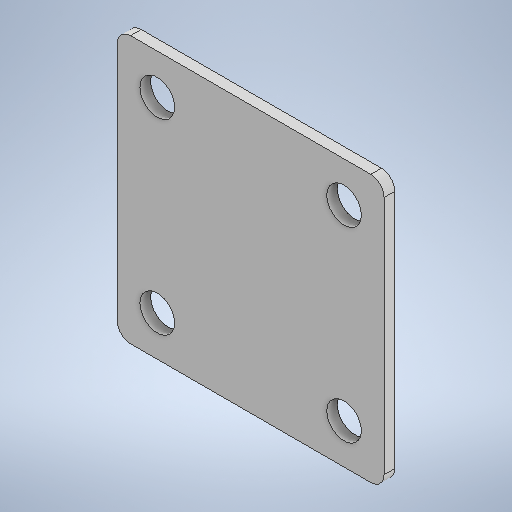
# Autodesk Inventor part: GBK-RK-0832 ring plate
Saved by Autodesk Inventor 2026 (Build 300175000, 175)
## iProperties
Created: 2024-05-23
Part Number: GBK-RK-0832 ring plate
Material: Generic
Document SubType Name: Sheet Metal
Designer: user
Mass: 0.559799 g
Surface Area: 23.3947 cm^2
Volume: 0.559799 cm^3
Density: 1 g/cm^3
Flat Pattern Width: 10 cm
Flat Pattern Length: 10 cm
Flat Pattern Area: 100 cm^2
Sheet Metal Rule: По умолчанию_мм
Sheet Metal Width: 100,000 мм
Sheet Metal Length: 100,000 мм
Sheet Metal Area: 10000,000 мм^2
Appearance: По умолчанию
Author: admin
Autodesk Inventor part; units mm, degrees
ref_plane "YZ Plane" through (0, 0, 0) normal (1, 0, 0) x (0, 1, 0)
ref_plane "XZ Plane" through (0, 0, 0) normal (0, 1, 0) x (-1, 0, 0)
ref_plane "XY Plane" through (0, 0, 0) normal (0, 0, 1) x (1, 0, 0)
sketch "Sketch1" plane through (0, 0, 0) normal (0, 0, 1) x (1, 0, 0)
  line L0 (-45, 50) -> (45, 50)
  line L1 (50, 45) -> (50, -45)
  line L2 (45, -50) -> (-45, -50)
  line L3 (-50, -45) -> (-50, 45)
  line L4 (-50, 50) -> (50, -50) construction
  line L5 (50, 50) -> (-50, -50) construction
  line L6 (0, 50) -> (0, -50) construction
  circle A0 centre (-35, -35) radius 6.5
  circle A1 centre (-35, 35) radius 6.5
  circle A2 centre (35, -35) radius 6.5
  circle A3 centre (35, 35) radius 6.5
  line L7 (35, 35) -> (-35, 35) construction
  line L8 (-35, 35) -> (-35, -35) construction
  line L9 (-35, -35) -> (35, -35) construction
  line L10 (35, -35) -> (35, 35) construction
  line L11 (35, 35) -> (-35, -35) construction
  line L12 (-35, 35) -> (35, -35) construction
  arc A4 (-45, 50) -> (-50, 45) centre (-45, 45) ccw
  arc A5 (50, 45) -> (45, 50) centre (45, 45) ccw
  arc A6 (45, -50) -> (50, -45) centre (45, -45) ccw
  arc A7 (-50, -45) -> (-45, -50) centre (-45, -45) ccw
  point P0 (0, 0)
  dimension "d0" = 100
  dimension "d1" = 100
  dimension "d19" = 13
  dimension "d20" = 70
  dimension "d42" = 5
  measures "d0" distance of L4.end L5.end
  measures "d1" distance of L5.start L4.end
  measures "d19" diameter of A0
  measures "d20" distance of L8.end L9.end
  measures "d42" radius of A4
extrude "Plate1" add sketch "Sketch1" along normal blind 4
equation "\"d0\" = d1"
equation "\"d2\" = Thickness"
equation "\"BendRadius\" = Thickness"
equation "\"BendReliefWidth\" = Thickness"
equation "\"BendReliefDepth\" = 0.5 * Thickness"
equation "\"CornerReliefSize\" = 4 * Thickness"
equation "\"MinimumRemnant\" = 2 * Thickness"
equation "\"TransitionRadius\" = BendRadius"
equation "\"JacobiRadiusSize\" = BendRadius"
equation "\"GapSize\" = Thickness"
equation "\"Thickness\" = 4"
body "Solid1"
